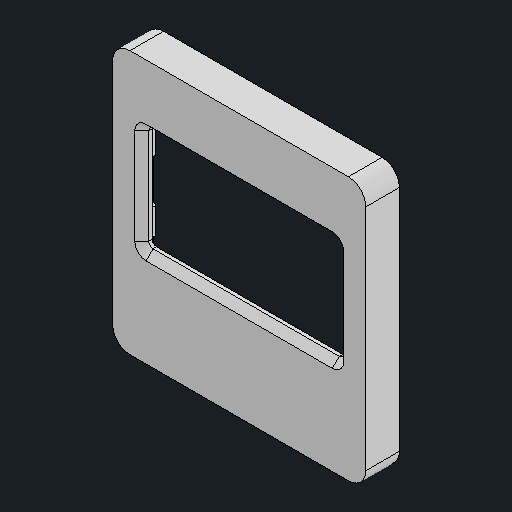
# Autodesk Inventor part: sensor-box-oled-cover-trial
Saved by Autodesk Inventor 2027.1 (Build 311270010, 270A)
## iProperties
Created: 2026-10-26
Part Number: sensor-box-oled-cover-trial
Material: Generic
Description: Trial low-lip friction-fit OLED cover; grips PCB edges, clears glass and bolts
Document SubType Name: Modeling
Designer: queezz
Density: 1 g/cm^3
Appearance: Default
Mass: 0.903855 g
Surface Area: 20.494 cm^2
Volume: 0.903855 cm^3
Author: queezz
Autodesk Inventor part; units mm, degrees
ref_plane "Outer cover envelope plane" through (0, 0, -1.1) normal (0, 0, 1) x (1, 0, 0)
sketch "Outer cover envelope" plane through (0, 0, -1.1) normal (0, 0, 1) x (1, 0, 0)
  line L0 (-14.55, -15.13) -> (14.55, -15.13)
  line L1 (14.55, -15.13) -> (14.55, 15.13)
  line L2 (14.55, 15.13) -> (-14.55, 15.13)
  line L3 (-14.55, 15.13) -> (-14.55, -15.13)
  point P0 (0, 0)
  dimension "d1" = 29.1
  dimension "d2" = 30.26
  dimension "d3" = 14.55
  dimension "d4" = 15.13
  constraints: 8 end point, 2 parallel, 1 horizontal, 1 perpendicular, 1 other
  measures "d1" distance of L0.start L0.end
  measures "d2" distance of L0.end L1.end
  measures "d3" horizontal distance of point (0, 0) L0.start
  measures "d4" vertical distance of point (0, 0) L0.start
extrude "Cover envelope" add sketch "Outer cover envelope" along normal blind 3.865
fillet "Rounded outside corners" radius 2 4 edges at (-14.55, -15.13, 0.8325) (-14.55, 15.13, 0.8325) (14.55, 15.13, 0.8325) (14.55, -15.13, 0.8325)
ref_plane "PCB clearance cavity plane" through (0, 0, -1.1) normal (0, 0, 1) x (1, 0, 0)
sketch "PCB clearance cavity" plane through (0, 0, -1.1) normal (0, 0, 1) x (1, 0, 0)
  line L0 (-13.75, -14.33) -> (13.75, -14.33)
  line L1 (13.75, -14.33) -> (13.75, 14.33)
  line L2 (13.75, 14.33) -> (-13.75, 14.33)
  line L3 (-13.75, 14.33) -> (-13.75, -14.33)
  point P0 (0, 0)
  dimension "d9" = 27.5
  dimension "d10" = 28.66
  dimension "d11" = 13.75
  dimension "d12" = 14.33
  constraints: 8 end point, 2 parallel, 1 horizontal, 1 perpendicular, 1 other
  measures "d9" distance of L0.start L0.end
  measures "d10" distance of L0.end L1.end
  measures "d11" horizontal distance of point (0, 0) L0.start
  measures "d12" vertical distance of point (0, 0) L0.start
extrude "Underside cavity" cut sketch "PCB clearance cavity" along normal blind 2.665
fillet "Constant-wall inner corners" radius 1.2 4 edges at (-13.75, 14.33, 0.2325) (-13.75, -14.33, 0.2325) (13.75, 14.33, 0.2325) (13.75, -14.33, 0.2325)
ref_plane "OLED viewing window plane" through (0, 0, 1.565) normal (0, 0, 1) x (1, 0, 0)
sketch "OLED viewing window" plane through (0, 0, 1.565) normal (0, 0, 1) x (1, 0, 0)
  line L0 (-11.2, -4.07) -> (11.2, -4.07)
  line L1 (11.2, -4.07) -> (11.2, 7.93)
  line L2 (11.2, 7.93) -> (-11.2, 7.93)
  line L3 (-11.2, 7.93) -> (-11.2, -4.07)
  point P0 (0, 0)
  dimension "d17" = 22.4
  dimension "d18" = 12
  dimension "d19" = 11.2
  dimension "d20" = 4.07
  constraints: 8 end point, 2 parallel, 1 horizontal, 1 perpendicular, 1 other
  measures "d17" distance of L0.start L0.end
  measures "d18" distance of L0.end L1.end
  measures "d19" horizontal distance of point (0, 0) L0.start
  measures "d20" vertical distance of point (0, 0) L0.start
extrude "OLED viewing opening" cut sketch "OLED viewing window" along normal blind 1.2
fillet "Window corner radius" radius 0.5 4 edges at (-11.2, 7.93, 2.165) (-11.2, -4.07, 2.165) (11.2, 7.93, 2.165) (11.2, -4.07, 2.165)
chamfer "Low viewing lip bevel" distance 0.8 angle 45 8 edges at (11.0536, -3.9236, 2.765) (0, -4.07, 2.765) (11.0536, 7.7836, 2.765) (11.2, 1.93, 2.765) (-11.0536, -3.9236, 2.765) (-11.2, 1.93, 2.765) (-11.0536, 7.7836, 2.765) (0, 7.93, 2.765)
ref_plane "Four screw head clearances plane" through (0, 0, -1.1) normal (0, 0, 1) x (1, 0, 0)
sketch "Four screw head clearances" plane through (0, 0, -1.1) normal (0, 0, 1) x (1, 0, 0)
  circle A0 centre (-11.55, -12.13) radius 2.2
  circle A1 centre (-11.55, 11.43) radius 2.2
  circle A2 centre (11.55, 11.43) radius 2.2
  circle A3 centre (11.55, -12.13) radius 2.2
  point P0 (0, 0)
  dimension "d28" = 4.4
  dimension "d29" = 11.55
  dimension "d30" = 12.13
  dimension "d31" = 4.4
  dimension "d32" = 11.55
  dimension "d33" = 11.43
  dimension "d34" = 4.4
  dimension "d35" = 11.55
  dimension "d36" = 11.43
  dimension "d37" = 4.4
  dimension "d38" = 11.55
  dimension "d39" = 12.13
  constraints: 4 centre point, 1 other
  measures "d28" diameter of A0
  measures "d29" horizontal distance of point (0, 0) A0.centre
  measures "d30" vertical distance of point (0, 0) A0.centre
  measures "d31" diameter of A1
  measures "d32" horizontal distance of point (0, 0) A1.centre
  measures "d33" vertical distance of point (0, 0) A1.centre
  measures "d34" diameter of A2
  measures "d35" horizontal distance of point (0, 0) A2.centre
  measures "d36" vertical distance of point (0, 0) A2.centre
  measures "d37" diameter of A3
  measures "d38" horizontal distance of point (0, 0) A3.centre
  measures "d39" vertical distance of point (0, 0) A3.centre
extrude "Hidden screw head pockets" cut sketch "Four screw head clearances" along normal blind 3.065
ref_plane "Terminal cover clearance plane" through (0, 0, 1.565) normal (0, 0, 1) x (1, 0, 0)
sketch "Terminal cover clearance" plane through (0, 0, 1.565) normal (0, 0, 1) x (1, 0, 0)
  line L0 (-5.5, 9.5753) -> (5.5, 9.5753)
  line L1 (5.5, 9.5753) -> (5.5, 13.5753)
  line L2 (5.5, 13.5753) -> (-5.5, 13.5753)
  line L3 (-5.5, 13.5753) -> (-5.5, 9.5753)
  point P0 (0, 0)
  dimension "d43" = 11
  dimension "d44" = 4
  dimension "d45" = 5.5
  dimension "d46" = 9.5753
  constraints: 8 end point, 2 parallel, 1 horizontal, 1 perpendicular, 1 other
  measures "d43" distance of L0.start L0.end
  measures "d44" distance of L0.end L1.end
  measures "d45" horizontal distance of point (0, 0) L0.start
  measures "d46" vertical distance of point (0, 0) L0.start
extrude "Hidden terminal clearance" cut sketch "Terminal cover clearance" along normal blind 0.4
ref_plane "Left friction pad -4 plane" through (0, 0, -1.1) normal (0, 0, 1) x (1, 0, 0)
sketch "Left friction pad -4" plane through (0, 0, -1.1) normal (0, 0, 1) x (1, 0, 0)
  line L0 (-13.8, -5.5) -> (-13.3, -5.5)
  line L1 (-13.3, -5.5) -> (-13.3, -2.5)
  line L2 (-13.3, -2.5) -> (-13.8, -2.5)
  line L3 (-13.8, -2.5) -> (-13.8, -5.5)
  point P0 (0, 0)
  dimension "d50" = 0.5
  dimension "d51" = 3
  dimension "d52" = 13.8
  dimension "d53" = 5.5
  constraints: 8 end point, 2 parallel, 1 horizontal, 1 perpendicular, 1 other
  measures "d50" distance of L0.start L0.end
  measures "d51" distance of L0.end L1.end
  measures "d52" horizontal distance of point (0, 0) L0.start
  measures "d53" vertical distance of point (0, 0) L0.start
extrude "PCB edge friction pad -1 -4" add sketch "Left friction pad -4" along normal blind 0.65
ref_plane "Left friction pad 4 plane" through (0, 0, -1.1) normal (0, 0, 1) x (1, 0, 0)
sketch "Left friction pad 4" plane through (0, 0, -1.1) normal (0, 0, 1) x (1, 0, 0)
  line L0 (-13.8, 2.5) -> (-13.3, 2.5)
  line L1 (-13.3, 2.5) -> (-13.3, 5.5)
  line L2 (-13.3, 5.5) -> (-13.8, 5.5)
  line L3 (-13.8, 5.5) -> (-13.8, 2.5)
  point P0 (0, 0)
  dimension "d57" = 0.5
  dimension "d58" = 3
  dimension "d59" = 13.8
  dimension "d60" = 2.5
  constraints: 8 end point, 2 parallel, 1 horizontal, 1 perpendicular, 1 other
  measures "d57" distance of L0.start L0.end
  measures "d58" distance of L0.end L1.end
  measures "d59" horizontal distance of point (0, 0) L0.start
  measures "d60" vertical distance of point (0, 0) L0.start
extrude "PCB edge friction pad -1 4" add sketch "Left friction pad 4" along normal blind 0.65
ref_plane "Right friction pad -4 plane" through (0, 0, -1.1) normal (0, 0, 1) x (1, 0, 0)
sketch "Right friction pad -4" plane through (0, 0, -1.1) normal (0, 0, 1) x (1, 0, 0)
  line L0 (13.3, -5.5) -> (13.8, -5.5)
  line L1 (13.8, -5.5) -> (13.8, -2.5)
  line L2 (13.8, -2.5) -> (13.3, -2.5)
  line L3 (13.3, -2.5) -> (13.3, -5.5)
  point P0 (0, 0)
  dimension "d64" = 0.5
  dimension "d65" = 3
  dimension "d66" = 13.3
  dimension "d67" = 5.5
  constraints: 8 end point, 2 parallel, 1 horizontal, 1 perpendicular, 1 other
  measures "d64" distance of L0.start L0.end
  measures "d65" distance of L0.end L1.end
  measures "d66" horizontal distance of point (0, 0) L0.start
  measures "d67" vertical distance of point (0, 0) L0.start
extrude "PCB edge friction pad 1 -4" add sketch "Right friction pad -4" along normal blind 0.65
ref_plane "Right friction pad 4 plane" through (0, 0, -1.1) normal (0, 0, 1) x (1, 0, 0)
sketch "Right friction pad 4" plane through (0, 0, -1.1) normal (0, 0, 1) x (1, 0, 0)
  line L0 (13.3, 2.5) -> (13.8, 2.5)
  line L1 (13.8, 2.5) -> (13.8, 5.5)
  line L2 (13.8, 5.5) -> (13.3, 5.5)
  line L3 (13.3, 5.5) -> (13.3, 2.5)
  point P0 (0, 0)
  dimension "d71" = 0.5
  dimension "d72" = 3
  dimension "d73" = 13.3
  dimension "d74" = 2.5
  constraints: 8 end point, 2 parallel, 1 horizontal, 1 perpendicular, 1 other
  measures "d71" distance of L0.start L0.end
  measures "d72" distance of L0.end L1.end
  measures "d73" horizontal distance of point (0, 0) L0.start
  measures "d74" vertical distance of point (0, 0) L0.start
extrude "PCB edge friction pad 1 4" add sketch "Right friction pad 4" along normal blind 0.65
chamfer "Gentle lead ins on PCB friction pads" distance 0.15 angle 45 4 edges at (13.3, 4, -1.1) (-13.3, 4, -1.1) (-13.3, -4, -1.1) (13.3, -4, -1.1)
equation "\"d1\" = outer_width"
equation "\"d2\" = outer_height"
equation "\"d3\" = 0.5 * outer_width"
equation "\"d4\" = 0.5 * outer_height"
equation "\"d5\" = cover_top - skirt_bottom"
equation "\"d7\" = outer_corner_radius"
equation "\"d9\" = cavity_width"
equation "\"d10\" = cavity_height"
equation "\"d11\" = 0.5 * cavity_width"
equation "\"d12\" = 0.5 * cavity_height"
equation "\"d13\" = face_bottom - skirt_bottom"
equation "\"d15\" = inner_corner_radius"
equation "\"d21\" = face_thickness"
equation "\"d23\" = window_corner_radius"
equation "\"d24\" = window_bevel"
equation "\"d25\" = window_bevel"
equation "\"d28\" = bolt_clearance_diameter"
equation "\"d31\" = bolt_clearance_diameter"
equation "\"d34\" = bolt_clearance_diameter"
equation "\"d37\" = bolt_clearance_diameter"
equation "\"d40\" = bolt_pocket_top - skirt_bottom"
equation "\"d43\" = header_pocket_width"
equation "\"d44\" = header_pocket_height"
equation "\"d45\" = 0.5 * header_pocket_width"
equation "\"d46\" = header_center_y - 0.5 * header_pocket_height"
equation "\"d47\" = bolt_pocket_top - face_bottom"
equation "\"d50\" = pad_width"
equation "\"d52\" = 0.5 * cavity_width + pad_overlap"
equation "\"d54\" = pad_height"
equation "\"d57\" = pad_width"
equation "\"d59\" = 0.5 * cavity_width + pad_overlap"
equation "\"d61\" = pad_height"
equation "\"d64\" = pad_width"
equation "\"d68\" = pad_height"
equation "\"d71\" = pad_width"
equation "\"d75\" = pad_height"
equation "\"d77\" = pad_lead_in"
equation "\"d78\" = pad_lead_in"
equation "\"pcb_width\" = 26.7"
equation "\"pcb_height\" = 27.86"
equation "\"screen_height\" = 1.265"
equation "\"bolt_head_height\" = 1.765"
equation "\"skirt_bottom\" = -1.1"
equation "\"face_bottom\" = 1.565"
equation "\"cover_top\" = 2.765"
equation "\"face_thickness\" = cover_top - face_bottom"
equation "\"cavity_width\" = 27.5"
equation "\"cavity_height\" = 28.66"
equation "\"outer_width\" = 29.1"
equation "\"outer_height\" = 30.26"
equation "\"outer_corner_radius\" = 2"
equation "\"inner_corner_radius\" = 1.2"
equation "\"window_center_y\" = 1.93"
equation "\"window_corner_radius\" = 0.5"
equation "\"window_bevel\" = 0.8"
equation "\"outer_face_above_glass\" = cover_top - screen_height"
equation "\"bolt_clearance_diameter\" = 4.4"
equation "\"bolt_pocket_top\" = 1.965"
equation "\"pad_overlap\" = 0.05"
equation "\"pad_width\" = 0.5"
equation "\"pad_top\" = -0.45"
equation "\"pad_height\" = pad_top - skirt_bottom"
equation "\"header_pocket_width\" = 11"
equation "\"header_pocket_height\" = 4"
equation "\"d0\" = skirt_bottom"
equation "\"d8\" = skirt_bottom"
equation "\"d16\" = face_bottom"
equation "\"d27\" = skirt_bottom"
equation "\"header_center_y\" = 11.5753"
equation "\"d42\" = face_bottom"
equation "\"d49\" = skirt_bottom"
equation "\"d56\" = skirt_bottom"
equation "\"d63\" = skirt_bottom"
equation "\"d70\" = skirt_bottom"
equation "\"pad_lead_in\" = 0.15"
body "Solid1"
